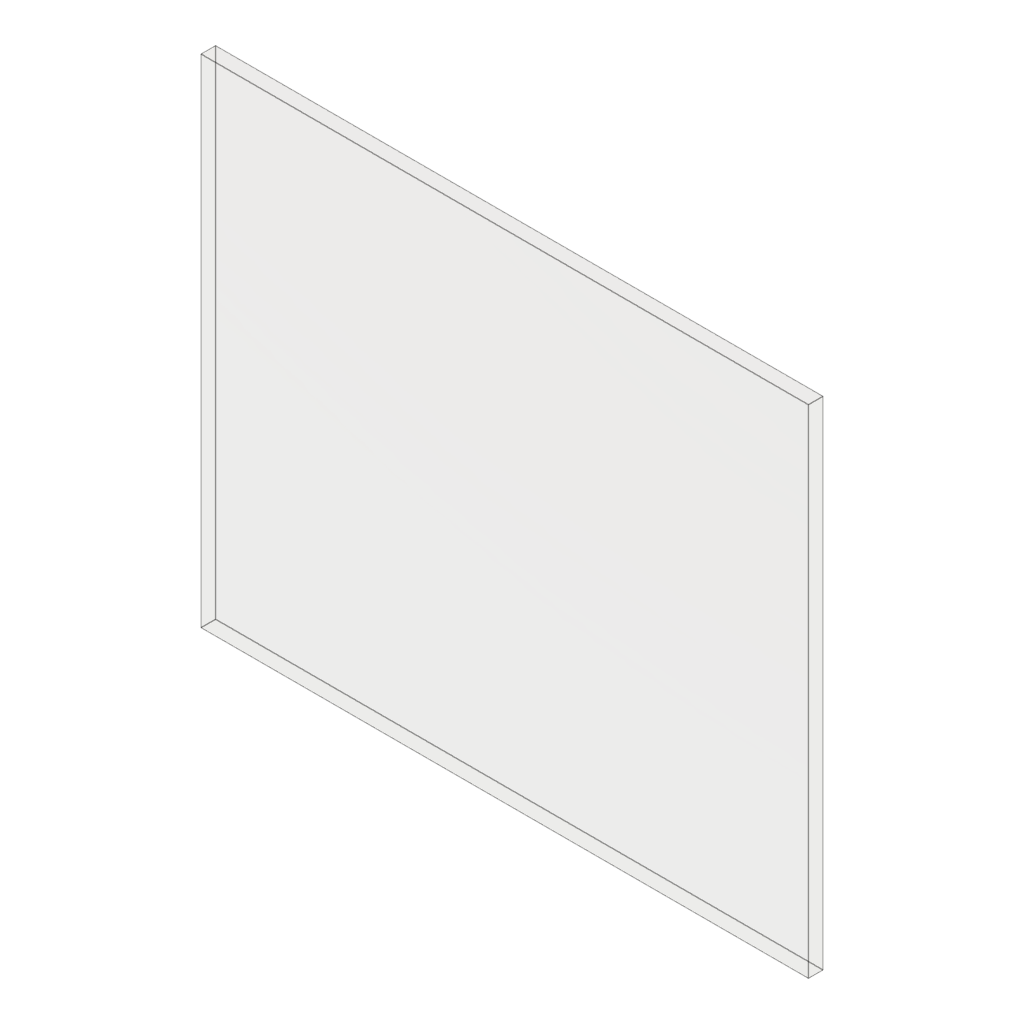
02-17 Door Window v2 (Autodesk Fusion 360 design; units mm, degrees)
Autodesk Fusion 360 part; units mm, degrees
sketch "Sketch1" plane through (0, 0, 0) normal (0, 1, 0) x (1, 0, 0)
  line L0 (0, 0) -> (4185, 0)
  line L1 (4185, 0) -> (4185, -3423)
  line L2 (4185, -3423) -> (0, -3423)
  line L3 (0, -3423) -> (0, 0)
  dimension "d1" = 3423
  dimension "d2" = 4185
  constraint horizontal L0
  constraint vertical L1
  constraint horizontal L2
  constraint vertical L3
  constraint coincident L0.start L3.end
  measures "d1" distance of L0.end L1.end
  measures "d2" distance of L0.start L0.end
extrude "Extrude1" add sketch "Sketch1" along normal blind 101.6
scale "Scale1" factor 0.03937 about (0, 0, 3423) bodies 1
move_body "Move1" bodies 1 to x (1, 0, 0) y (0, 1, 0) z (0, 0, 1) at (0, 0, -3288.2362)
equation "d3 = 4 * 25.4 mm"
equation "d5 = 1 / 25.4"
